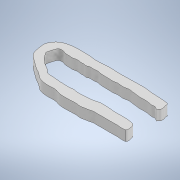
# Autodesk Inventor part: litera_c
Saved by Autodesk Inventor 2022.6 (Build 266554000, 554)
## iProperties
Created: 2024-11-29
Part Number: litera_c
Material: Generic
Document SubType Name: Modeling
Designer: Dragos Macovei
Density: 1 g/cm^3
Appearance: Default
Author: Dragos Macovei
Autodesk Inventor part; units mm, degrees
ref_plane "YZ Plane" through (0, 0, 0) normal (1, 0, 0) x (0, 1, 0)
ref_plane "XZ Plane" through (0, 0, 0) normal (0, 1, 0) x (-1, 0, 0)
ref_plane "XY Plane" through (0, 0, 0) normal (0, 0, 1) x (1, 0, 0)
sketch "Sketch1" plane through (0, 0, 0) normal (0, 1, 0) x (-1, 0, 0)
  line L0 (0, 0) -> (40, 0)
  line L1 (40, 0) -> (40, 40)
  line L2 (40, 40) -> (0, 40)
  line L3 (0, 40) -> (0, 0)
  line L4 (-155.7912, 103.9867) -> (161.0121, 103.9867) construction
  line L5 (161.0121, 103.9867) -> (161.0121, -318.4176) construction
  line L6 (161.0121, -318.4176) -> (-155.7912, -318.4176) construction
  line L7 (-155.7912, -318.4176) -> (-155.7912, 103.9867) construction
  spline S0 degree 5 poles (3.8266, 27.0843) (3.9577, 27.1463) (4.2253, 27.1914) (4.7078, 27.1323) (5.4419, 27.2631) (5.9879, 26.9706) (7.1881, 27.1426) (8.0906, 27.0594) (9.0875, 27.0896) (10.1049, 27.0997) (11.2977, 27.0294) (12.7744, 27.2126) (13.2951, 26.8321) (14.7611, 27.5982) (15.4701, 27.3093) (16.6587, 28.0553) (17.6832, 27.3778) (19.24, 27.6964) (21.387, 27.6681) (23.3535, 27.7681) (24.485, 26.7975) (26.199, 27.1756) (27.3569, 27.1161) (29.508, 26.9268) (30.4047, 26.2492) (31.6062, 25.0794) (33.0204, 24.6475) (34.2465, 23.5502) (35.115, 22.9786) (36.3302, 22.1142) (37.4126, 21.2439) (37.8015, 20.0092) (37.9257, 18.4392) (38.416, 17.2935) (37.7491, 15.4417) (36.1924, 13.7564) (34.0464, 13.4758) (32.6038, 13.11) (30.3713, 13.353) (27.9655, 13.1055) (26.9289, 13.6548) (24.8948, 13.447) (21.8703, 13.1255) (20.3354, 13.5444) (15.5158, 13.2678) (13.5199, 13.3685) (11.4424, 13.1381) (9.3939, 13.7471) (6.9542, 13.5865) (5.4166, 13.8962) (3.6008, 13.8762) (4.5064, 14.864) (3.5487, 15.4571) (4.0404, 15.9237) (3.5032, 16.5305) (4.5099, 16.5556) (4.0816, 17.7247) (5.5453, 16.15) (5.8643, 17.0344) (7.007, 16.5546) (9.0113, 16.2701) (10.1217, 16.6852) (11.5852, 16.1792) (12.6587, 16.3305) (13.7491, 15.7801) (15.0277, 16.4181) (15.8833, 16.3226) (17.4264, 15.9386) (17.9644, 16.5716) (19.5222, 16.1767) (20.2438, 16.3854) (21.1747, 16.1986) (22.6813, 16.2988) (23.0833, 15.6953) (24.2554, 16.4773) (25.5263, 15.6619) (26.2721, 16.7215) (26.6411, 16.1356) (27.5919, 16.2798) (28.1953, 16.3658) (29.3071, 15.8079) (30.3029, 16.7415) (31.3115, 16.07) (32.2178, 16.4937) (33.1514, 16.0733) (33.6666, 15.8362) (34.8522, 15.9263) (35.0629, 16.4929) (35.2764, 17.0912) (35.4956, 17.8431) (35.6396, 18.4538) (35.8934, 18.9804) (35.2339, 19.5621) (34.7667, 20.4321) (34.5591, 20.736) (33.7751, 21.3265) (33.2443, 21.8587) (32.7611, 22.1763) (32.0993, 22.484) (31.6483, 22.861) (31.0498, 23.092) (30.808, 23.3214) (30.3877, 23.8103) (30.4738, 24.0759) (29.1026, 24.1318) (28.6517, 24.2737) (27.4509, 24.1289) (26.0958, 24.604) (25.2608, 24.2556) (23.9925, 24.6766) (22.1759, 24.325) (21.9635, 24.2912) (20.3251, 24.7365) (18.9258, 24.4182) (17.5397, 24.4767) (15.9503, 24.2935) (14.6255, 23.605) (13.103, 23.9251) (12.1768, 23.7246) (10.3849, 24.1903) (9.2921, 23.9468) (7.6415, 24.118) (6.6371, 23.9099) (5.6058, 24.2305) (4.4533, 24.1761) (3.6589, 24.7923) (3.748, 25.6922) (3.3973, 26.4336) (3.522, 26.8628) (3.6989, 27.0239) (3.8266, 27.0843) knots 0 0 0 0 0 0 0.007591 0.012962 0.019856 0.026999 0.034311 0.042105 0.050048 0.057822 0.065781 0.073614 0.081193 0.088595 0.096481 0.105054 0.114343 0.123922 0.133735 0.143493 0.152953 0.162025 0.171171 0.180442 0.18975 0.198651 0.207589 0.216421 0.225046 0.233623 0.242261 0.25109 0.26045 0.270275 0.280273 0.290852 0.301653 0.311843 0.321833 0.332324 0.342951 0.35455 0.366822 0.379192 0.391361 0.403519 0.414645 0.424589 0.4337 0.441774 0.448489 0.454022 0.459453 0.464676 0.470034 0.475647 0.481752 0.488975 0.49704 0.505496 0.514225 0.523091 0.531422 0.539469 0.547453 0.555315 0.563291 0.571029 0.578703 0.586381 0.593875 0.601285 0.609035 0.616543 0.623366 0.630178 0.636682 0.642983 0.649671 0.656891 0.664325 0.671855 0.679156 0.686225 0.692881 0.699277 0.705604 0.711818 0.71766 0.723691 0.729969 0.736051 0.742332 0.748915 0.755378 0.761643 0.76801 0.774093 0.779784 0.785278 0.79031 0.795462 0.800942 0.807033 0.813907 0.821486 0.829518 0.837911 0.845913 0.853773 0.862034 0.870348 0.878776 0.887878 0.897059 0.905934 0.91484 0.923628 0.932418 0.941059 0.949644 0.957927 0.965783 0.973244 0.980544 0.987364 0.992614 1 1 1 1 1 1
  point P0 (5.2872, 27.1702)
  point P1 (5.9746, 27.0843)
  point P2 (7.0487, 27.0843)
  point P3 (8.0797, 27.0843)
  point P4 (9.0249, 27.0843)
  point P5 (10.056, 27.0843)
  point P6 (11.3878, 27.0843)
  point P7 (12.6766, 27.0843)
  point P8 (13.4929, 27.0843)
  point P9 (14.6528, 27.385)
  point P10 (15.5121, 27.5139)
  point P11 (16.4572, 27.7287)
  point P12 (17.4883, 27.6428)
  point P13 (18.992, 27.5998)
  point P14 (21.3978, 27.6857)
  point P15 (23.374, 27.4709)
  point P16 (24.7058, 27.0843)
  point P17 (26.0806, 27.0843)
  point P18 (27.4983, 27.0843)
  point P19 (29.3027, 26.7835)
  point P20 (30.4627, 26.1391)
  point P21 (31.6656, 25.2369)
  point P22 (33.0404, 24.4636)
  point P23 (34.2433, 23.6044)
  point P24 (35.1884, 22.917)
  point P25 (36.3054, 22.1007)
  point P26 (37.2506, 21.1556)
  point P27 (37.7232, 20)
  point P28 (37.9809, 18.6209)
  point P29 (38.1528, 17.375)
  point P30 (37.6802, 15.7424)
  point P31 (36.0906, 14.1099)
  point P32 (34.1574, 13.4655)
  point P33 (32.4819, 13.2507)
  point P34 (30.2049, 13.2507)
  point P35 (28.0998, 13.2936)
  point P36 (26.8969, 13.4655)
  point P37 (25.2214, 13.4655)
  point P38 (22.5578, 13.2936)
  point P39 (20, 13.3796)
  point P40 (15.598, 13.3366)
  point P41 (13.1922, 13.2936)
  point P42 (11.3448, 13.3366)
  point P43 (9.1108, 13.5944)
  point P44 (6.5761, 13.7233)
  point P45 (4.5999, 13.9381)
  point P46 (4.1273, 14.2818)
  point P47 (4.0843, 14.9262)
  point P48 (3.8266, 15.5276)
  point P49 (3.8266, 16.0002)
  point P50 (3.8266, 16.3869)
  point P51 (4.1702, 16.7306)
  point P52 (4.385, 17.1172)
  point P53 (5.1154, 16.7735)
  point P54 (5.8457, 16.6876)
  point P55 (6.7479, 16.6876)
  point P56 (8.8101, 16.4298)
  point P57 (10.3137, 16.4728)
  point P58 (11.6455, 16.3009)
  point P59 (12.7196, 16.1721)
  point P60 (13.7936, 16.0432)
  point P61 (14.9536, 16.258)
  point P62 (16.0276, 16.258)
  point P63 (17.2735, 16.1721)
  point P64 (18.1757, 16.3439)
  point P65 (19.4216, 16.3009)
  point P66 (20.2808, 16.3009)
  point P67 (21.2689, 16.258)
  point P68 (22.5148, 16.1291)
  point P69 (23.2022, 16.0002)
  point P70 (24.3192, 16.1291)
  point P71 (25.651, 16.1291)
  point P72 (26.2954, 16.3869)
  point P73 (26.725, 16.3009)
  point P74 (27.4124, 16.258)
  point P75 (28.1428, 16.258)
  point P76 (29.1738, 16.1291)
  point P77 (30.3338, 16.3869)
  point P78 (31.3649, 16.3009)
  point P79 (32.31, 16.3009)
  point P80 (33.1263, 16.0861)
  point P81 (33.8566, 15.9143)
  point P82 (34.7159, 16.0861)
  point P83 (35.0596, 16.5158)
  point P84 (35.2744, 17.1172)
  point P85 (35.4892, 17.8476)
  point P86 (35.661, 18.449)
  point P87 (35.704, 18.9216)
  point P88 (35.3173, 19.566)
  point P89 (34.8018, 20.3393)
  point P90 (34.4581, 20.7689)
  point P91 (33.8137, 21.3274)
  point P92 (33.2122, 21.843)
  point P93 (32.6967, 22.1867)
  point P94 (32.0952, 22.5304)
  point P95 (31.5367, 22.8741)
  point P96 (31.0641, 23.1318)
  point P97 (30.7634, 23.3896)
  point P98 (30.5056, 23.7333)
  point P99 (30.3338, 23.9481)
  point P100 (29.5605, 24.1199)
  point P101 (28.6583, 24.2059)
  point P102 (27.5843, 24.2488)
  point P103 (26.2095, 24.4207)
  point P104 (25.2214, 24.4207)
  point P105 (23.8036, 24.5066)
  point P106 (22.3859, 24.3777)
  point P107 (21.7845, 24.3777)
  point P108 (20.6245, 24.5496)
  point P109 (19.0349, 24.5066)
  point P110 (17.5313, 24.4207)
  point P111 (15.9417, 24.1629)
  point P112 (14.481, 23.8192)
  point P113 (13.1922, 23.8192)
  point P114 (12.0752, 23.8622)
  point P115 (10.5285, 24.034)
  point P116 (9.1108, 24.034)
  point P117 (7.6072, 24.034)
  point P118 (6.5331, 24.034)
  point P119 (5.502, 24.1629)
  point P120 (4.428, 24.3777)
  point P121 (3.8266, 24.9362)
  point P122 (3.6117, 25.8384)
  point P123 (3.5258, 26.6976)
  dimension "d0" = 40
  dimension "d1" = 40
  constraints: 8 end point, 2 parallel, 1 horizontal, 1 perpendicular, 128 other
  measures "d0" distance of L2.end L1.end
  measures "d1" distance of L1.end L0.end
extrude "Extrusion1" add sketch "Sketch1" along normal blind 3 contours S0
body "Solid1"
